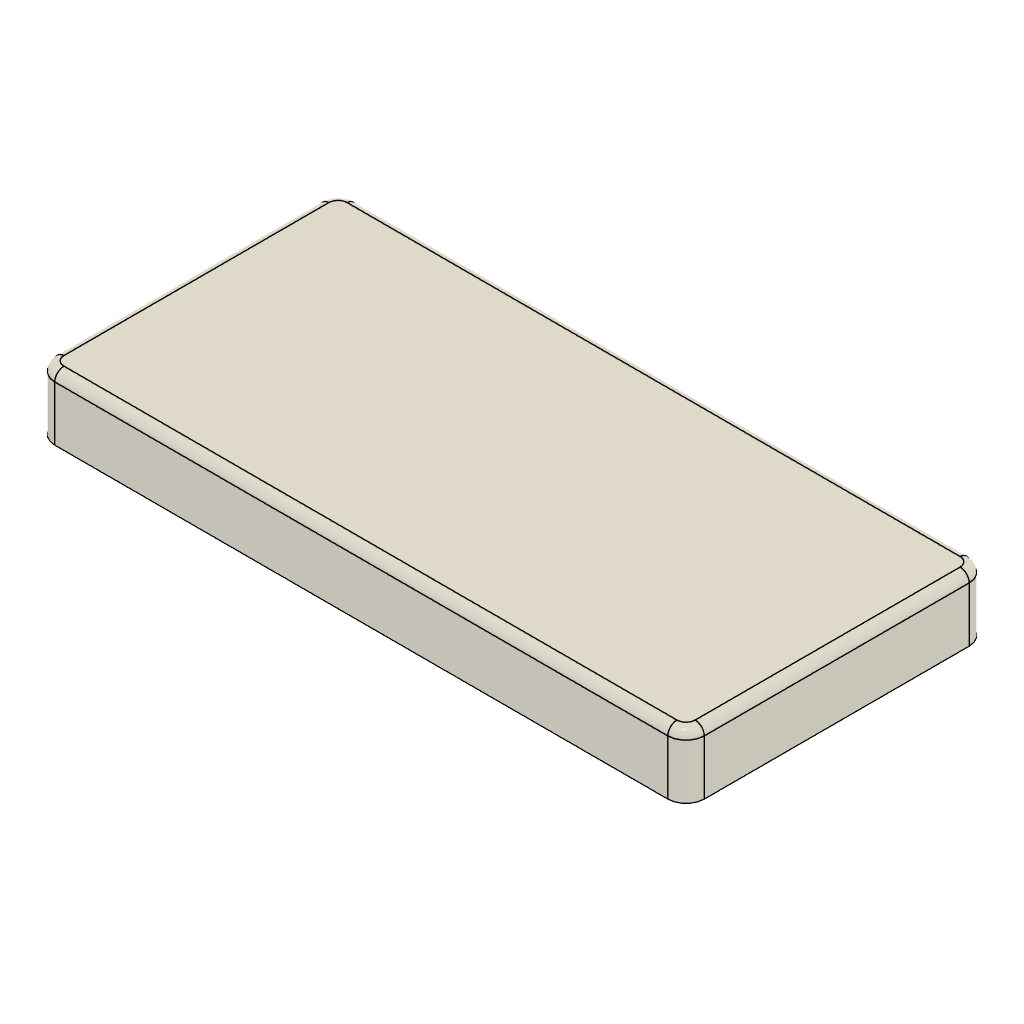
Keycap (2u) (Autodesk Fusion 360 archive; units mm, degrees)
design "Keycap (2u)" references "_Globals"
part number: 2026-10-16-15-07-42-335
Autodesk Fusion 360 part; units mm, degrees
derive "Derived from _Globals"
sketch "Sketch1" plane through (0, 0, 0) normal (0, 1, 0) x (1, 0, 0)
  line L0 (17.775, 8.25) -> (-17.775, 8.25)
  line L1 (-17.775, 8.25) -> (-17.775, -8.25)
  line L2 (-17.775, -8.25) -> (17.775, -8.25)
  line L3 (17.775, -8.25) -> (17.775, 8.25)
  line L4 (17.775, 8.25) -> (-17.775, -8.25) construction
  line L5 (-17.775, 8.25) -> (17.775, -8.25) construction
  dimension "d13" = 35.55
  dimension "d14" = 16.5
  constraint horizontal L0
  constraint perpendicular L0 L1
  constraint parallel L0 L2
  constraint parallel L1 L3
  constraint coincident L4 origin
  constraint coincident L5 origin
  measures "d13" distance of L1.end L2.end
  measures "d14" distance of L0.end L1.end
extrude "Extrude1" add sketch "Sketch1" along normal blind 3.5
fillet "Fillet1" radius 0.5 4 edges at (0, 3.5, -8.25) (17.775, 3.5, 0) (0, 3.5, 8.25) (-17.775, 3.5, 0)
fillet "Fillet2" radius 1 8 edges at (17.775, 1.5, -8.25) (17.6286, 3.3536, -8.1036) (-17.6286, 3.3536, -8.1036) (-17.775, 1.5, -8.25) (-17.6286, 3.3536, 8.1036) (-17.775, 1.5, 8.25) (17.6286, 3.3536, 8.1036) (17.775, 1.5, 8.25)
shell "Shell1" thickness 1 removed faces 1 at (5.5917, 0, 2.75)
fillet "Fillet3" radius 0.5 4 edges at (-16.775, 1.25, 7.25) (16.775, 1.25, 7.25) (16.775, 1.25, -7.25) (-16.775, 1.25, -7.25)
extrude "Extrude2" add 1 faces at (-5.425, 2.5, 2.4167) along direction (0, -1, 0) blind 0.45
sketch "Sketch2" plane through (0, 2.05, 0) normal (0, -1, 0) x (1, 0, 0)
  arc A0 (-16.775, -6.75) -> (-16.275, -7.25) centre (-16.275, -6.75) ccw
  line L0 (-16.275, -7.25) -> (16.275, -7.25)
  arc A1 (16.275, -7.25) -> (16.775, -6.75) centre (16.275, -6.75) ccw
  line L1 (16.775, -6.75) -> (16.775, 6.75)
  arc A2 (16.775, 6.75) -> (16.275, 7.25) centre (16.275, 6.75) ccw
  line L2 (16.275, 7.25) -> (-16.275, 7.25)
  arc A3 (-16.275, 7.25) -> (-16.775, 6.75) centre (-16.275, 6.75) ccw
  line L3 (-16.775, 6.75) -> (-16.775, -6.75)
  line L4 (0, 0) -> (-12, 0) construction
  line L5 (-12, 0) -> (-12, 2.05) construction
  line L6 (-12.7, 2.05) -> (-11.3, 2.05)
  line L7 (-11.3, 2.05) -> (-11.3, 0.7)
  line L8 (-11.3, 0.7) -> (-9.95, 0.7)
  line L9 (-14.05, -0.7) -> (-14.05, 0.7)
  line L10 (-14.05, 0.7) -> (-12.7, 0.7)
  line L11 (-12.7, 0.7) -> (-12.7, 2.05)
  line L12 (-11.3, -2.05) -> (-12.7, -2.05)
  line L13 (-12.7, -2.05) -> (-12.7, -0.7)
  line L14 (-12.7, -0.7) -> (-14.05, -0.7)
  line L15 (-9.95, 0.7) -> (-9.95, -0.7)
  line L16 (-9.95, -0.7) -> (-11.3, -0.7)
  line L17 (-11.3, -0.7) -> (-11.3, -2.05)
  line L18 (0, 0) -> (0, 2.05) construction
  line L19 (0, 2.05) -> (-0.7, 2.05)
  line L20 (-0.7, 2.05) -> (-0.7, 0.7)
  line L21 (-0.7, 0.7) -> (-2.05, 0.7)
  line L22 (-2.05, 0.7) -> (-2.05, 0)
  line L23 (0, -2.05) -> (-0.7, -2.05)
  line L24 (-0.7, -2.05) -> (-0.7, -0.7)
  line L25 (-0.7, -0.7) -> (-2.05, -0.7)
  line L26 (-2.05, -0.7) -> (-2.05, 0)
  line L27 (12.7, 2.05) -> (11.3, 2.05)
  line L28 (11.3, 2.05) -> (11.3, 0.7)
  line L29 (11.3, 0.7) -> (9.95, 0.7)
  line L30 (9.95, 0.7) -> (9.95, -0.7)
  line L31 (11.3, -0.7) -> (11.3, -2.05)
  line L32 (9.95, -0.7) -> (11.3, -0.7)
  line L33 (11.3, -2.05) -> (12.7, -2.05)
  line L34 (12.7, -0.7) -> (14.05, -0.7)
  line L35 (12.7, -2.05) -> (12.7, -0.7)
  line L36 (14.05, -0.7) -> (14.05, 0.7)
  line L37 (12.7, 0.7) -> (12.7, 2.05)
  line L38 (14.05, 0.7) -> (12.7, 0.7)
  line L39 (0, 2.05) -> (0.7, 2.05)
  line L40 (0.7, 2.05) -> (0.7, 0.7)
  line L41 (2.05, 0.7) -> (2.05, 0)
  line L42 (0.7, 0.7) -> (2.05, 0.7)
  line L43 (0, -2.05) -> (0.7, -2.05)
  line L44 (0.7, -2.05) -> (0.7, -0.7)
  line L45 (2.05, -0.7) -> (2.05, 0)
  line L46 (0.7, -0.7) -> (2.05, -0.7)
  line L47 (-13.35, 2.7) -> (-10.65, 2.7)
  line L48 (-10.65, 2.7) -> (-10.65, 1.35)
  line L49 (-10.65, 1.35) -> (-9.3, 1.35)
  line L50 (-9.3, 1.35) -> (-9.3, -1.35)
  line L51 (-9.3, -1.35) -> (-10.65, -1.35)
  line L52 (-10.65, -1.35) -> (-10.65, -2.7)
  line L53 (-10.65, -2.7) -> (-13.35, -2.7)
  line L54 (-13.35, -2.7) -> (-13.35, -1.35)
  line L55 (-13.35, -1.35) -> (-14.7, -1.35)
  line L56 (-14.7, -1.35) -> (-14.7, 1.35)
  line L57 (-14.7, 1.35) -> (-13.35, 1.35)
  line L58 (-13.35, 1.35) -> (-13.35, 2.7)
  circle A4 centre (0, 0) radius 2.7
  line L59 (10.65, -2.7) -> (13.35, -2.7)
  line L60 (13.35, -2.7) -> (13.35, -1.35)
  line L61 (13.35, -1.35) -> (14.7, -1.35)
  line L62 (14.7, -1.35) -> (14.7, 1.35)
  line L63 (14.7, 1.35) -> (13.35, 1.35)
  line L64 (13.35, 1.35) -> (13.35, 2.7)
  line L65 (13.35, 2.7) -> (10.65, 2.7)
  line L66 (10.65, 2.7) -> (10.65, 1.35)
  line L67 (10.65, 1.35) -> (9.3, 1.35)
  line L68 (9.3, 1.35) -> (9.3, -1.35)
  line L69 (9.3, -1.35) -> (10.65, -1.35)
  line L70 (10.65, -1.35) -> (10.65, -2.7)
  dimension "d28" = 12
  dimension "d29" = 2.05
  dimension "d30" = 1.4
  dimension "d31" = 1.35
  dimension "d32" = 1.35
  dimension "d34" = 360
  dimension "d35" = 2.05
  dimension "d36" = 0.7
  dimension "d37" = 1.35
  dimension "d38" = 1.35
  dimension "d39" = -0.65
  dimension "d40" = 5.4
  dimension "d41" = 0.65
  constraint coincident L4.start L18.start
  constraint parallel L2 L4
  constraint perpendicular L4 L5
  constraint horizontal L6
  constraint midpoint L5.end L6
  constraint perpendicular L6 L7
  constraint perpendicular L7 L8
  constraint perpendicular L4 L18
  constraint perpendicular L18 L19
  constraint perpendicular L19 L20
  constraint perpendicular L20 L21
  constraint coincident L4 L22.end
  constraint perpendicular L4 L22
  constraint symmetric L4 L18.end L23.start
  constraint symmetric L4 L19.end L23.end
  constraint symmetric L4 L20.end L24.end
  constraint symmetric L4 L21.end L25.end
  constraint symmetric L4 L22.end L26.end
  constraint symmetric L6.start L18 L27.start
  constraint symmetric L6.end L18 L27.end
  constraint symmetric L7.end L18 L28.end
  constraint symmetric L8.end L18 L29.end
  constraint symmetric L9.start L18 L34.end
  constraint symmetric L9.end L18 L36.end
  constraint symmetric L10.end L18 L37.start
  constraint symmetric L12.start L18 L31.end
  constraint symmetric L12.end L18 L33.end
  constraint symmetric L13.end L18 L34.start
  constraint symmetric L15.end L18 L30.end
  constraint symmetric L16.end L18 L31.start
  constraint symmetric L19.start L18 L39.start
  constraint symmetric L18 L19.end L39.end
  constraint symmetric L18 L20.end L40.end
  constraint symmetric L18 L21.end L41.start
  constraint symmetric L18 L22.end L41.end
  constraint symmetric L18 L23.start L43.start
  constraint symmetric L18 L23.end L43.end
  constraint symmetric L18 L24.end L44.end
  constraint symmetric L18 L25.end L45.start
  measures "d28" distance of L4.start L4.end
  measures "d29" distance of L4.end L5.end
  measures "d30" distance of L6.start L6.end
  measures "d31" distance of L6.end L7.end
  measures "d32" distance of L7.end L8.end
  measures "d35" distance of L4.start L18.end
  measures "d36" distance of L18.end L19.end
  measures "d37" distance of L19.end L20.end
  measures "d38" distance of L20.end L21.end
  measures "d40" diameter of A4
extrude "Extrude3" add sketch "Sketch2" along normal blind 3.35 contours L47 L48 L49 L50 L51 L52 L53 L54 L55 L56 L57 L58 | A4 | L59 L60 L61 L62 L63 L64 L65 L66 L67 L68 L69 L70
fillet "Fillet4" radius 0.1 25 edges at (13.35, -1.3, -2.025) (14.025, -1.3, -1.35) (14.7, -1.3, 0) (14.025, -1.3, 1.35) (13.35, -1.3, 2.025) (12, -1.3, 2.7) (10.65, -1.3, 2.025) (9.975, -1.3, 1.35) (9.3, -1.3, 0) (9.975, -1.3, -1.35) (10.65, -1.3, -2.025) (12, -1.3, -2.7) (-2.5173, -1.3, -0.9764) (-9.3, -1.3, 0) (-9.975, -1.3, -1.35) (-10.65, -1.3, -2.025) (-12, -1.3, -2.7) (-13.35, -1.3, -2.025) (-14.025, -1.3, -1.35) (-14.7, -1.3, 0) (-14.025, -1.3, 1.35) (-13.35, -1.3, 2.025) (-12, -1.3, 2.7) (-10.65, -1.3, 2.025) (-9.975, -1.3, 1.35)
fillet "Fillet5" radius 0.1 24 edges at (10.65, 0.425, 2.7) (10.6793, -1.2707, 2.6707) (10.65, 0.425, 1.35) (10.6793, -1.2707, 1.3207) (9.3, 0.425, 1.35) (9.3293, -1.2707, 1.3207) (9.3, 0.425, -1.35) (9.3293, -1.2707, -1.3207) (10.65, 0.425, -1.35) (10.6793, -1.2707, -1.3207) (10.65, 0.425, -2.7) (10.6793, -1.2707, -2.6707) (13.35, 0.425, -2.7) (13.3207, -1.2707, -2.6707) (13.3207, -1.2707, -1.3207) (13.35, 0.425, -1.35) (14.6707, -1.2707, -1.3207) (14.7, 0.425, -1.35) (14.6707, -1.2707, 1.3207) (14.7, 0.425, 1.35) (13.3207, -1.2707, 1.3207) (13.35, 0.425, 1.35) (13.3207, -1.2707, 2.6707) (13.35, 0.425, 2.7)
fillet "Fillet6" radius 0.1 24 edges at (-10.6793, -1.2707, 1.3207) (-10.65, 0.425, 1.35) (-10.6793, -1.2707, 2.6707) (-10.65, 0.425, 2.7) (-13.3207, -1.2707, 2.6707) (-13.35, 0.425, 2.7) (-13.3207, -1.2707, 1.3207) (-13.35, 0.425, 1.35) (-14.6707, -1.2707, 1.3207) (-14.7, 0.425, 1.35) (-9.3293, -1.2707, 1.3207) (-9.3, 0.425, 1.35) (-10.6793, -1.2707, -1.3207) (-10.65, 0.425, -1.35) (-9.3293, -1.2707, -1.3207) (-9.3, 0.425, -1.35) (-10.6793, -1.2707, -2.6707) (-10.65, 0.425, -2.7) (-13.3207, -1.2707, -2.6707) (-13.35, 0.425, -2.7) (-13.3207, -1.2707, -1.3207) (-13.35, 0.425, -1.35) (-14.6707, -1.2707, -1.3207) (-14.7, 0.425, -1.35)
fillet "Fillet7" radius 0.1 12 edges at (-12.7, 0.375, -0.7) (-12.7, 0.375, 0.7) (-11.3, 0.375, 0.7) (-11.3, 0.375, -0.7) (0.7, 0.375, 0.7) (-0.7, 0.375, 0.7) (0.7, 0.375, -0.7) (-0.7, 0.375, -0.7) (11.3, 0.375, -0.7) (12.7, 0.375, -0.7) (12.7, 0.375, 0.7) (11.3, 0.375, 0.7)
equation "keycap_size_Ref = 16.5 mm"
equation "keycap_thickness_Ref = 3.5 mm" comment "Keycap thickness without stem"
equation "keycap_full_thickness_Ref = 4.8 mm" comment "Keycap thickness from stem to top"
equation "keycap_top_fillet_Ref = 0.5 mm"
equation "keycap_side_fillet_Ref = 1 mm"
equation "stem_fillet_Ref = 0.1 mm"
equation "stem_diameter_Ref = 5.5 mm"
equation "stem_cross_length_Ref = 4 mm"
equation "stem_cross_width_Ref = 1.3 mm"
equation "stem_offset_Ref = 0.1 mm"
equation "keycap_side_width_Ref = 1 mm"
equation "keycap_inner_thickness_Ref = keycap_full_thickness_Ref - 3.35 mm"
equation "d13 = keycap_size_Ref + switch_size_Ref"
equation "d14 = keycap_size_Ref"
equation "switch_size_Ref = 19.05 mm"
equation "d16 = keycap_thickness_Ref"
equation "d19 = keycap_top_fillet_Ref"
equation "d21 = keycap_side_fillet_Ref"
equation "d22 = keycap_side_width_Ref"
equation "d24 = keycap_side_fillet_Ref * 0.5"
equation "d25 = keycap_inner_thickness_Ref - keycap_side_width_Ref"
equation "stabilizer_distance = 12 mm"
equation "d28 = stabilizer_distance"
equation "d29 = ( stem_cross_length_Ref + stem_offset_Ref ) * 0.5"
equation "d30 = stem_cross_width_Ref + stem_offset_Ref"
equation "d31 = ( stem_cross_length_Ref - stem_cross_width_Ref ) * 0.5"
equation "d32 = ( stem_cross_length_Ref - stem_cross_width_Ref ) * 0.5"
equation "d35 = ( stem_cross_length_Ref + stem_offset_Ref ) * 0.5"
equation "d36 = ( stem_cross_width_Ref + stem_offset_Ref ) * 0.5"
equation "d37 = ( stem_cross_length_Ref - stem_cross_width_Ref ) * 0.5"
equation "d38 = ( stem_cross_length_Ref - stem_cross_width_Ref ) * 0.5"
equation "d39 = -( ( stem_diameter_Ref - stem_offset_Ref - ( stem_cross_length_Ref + stem_offset_Ref ) ) * 0.5 )"
equation "d40 = stem_diameter_Ref - stem_offset_Ref"
equation "d41 = ( ( stem_diameter_Ref - stem_offset_Ref - ( stem_cross_length_Ref + stem_offset_Ref ) ) * 0.5 )"
equation "d42 = keycap_full_thickness_Ref - keycap_inner_thickness_Ref"
equation "d45 = stem_fillet_Ref"
equation "d47 = stem_fillet_Ref"
equation "d49 = stem_fillet_Ref"
equation "d51 = stem_fillet_Ref"
named bodies: "Main"
